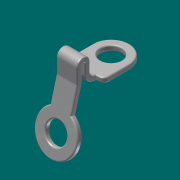
# Autodesk Inventor part: connector
Saved by Autodesk Inventor 2015 SP1 (Build 190203100, 203)
## iProperties
Created: 2015-06-26
Part Number: connector
Material: Generic
Document SubType Name: Modeling
Designer: Peter Mulkers
Density: 1 g/cm^3
Appearance: Steel
Author: Peter Mulkers
Autodesk Inventor part; units mm, degrees
ref_plane "YZ Plane" through (0, 0, 0) normal (1, 0, 0) x (0, 1, 0)
ref_plane "XZ Plane" through (0, 0, 0) normal (0, 1, 0) x (-1, 0, 0)
ref_plane "XY Plane" through (0, 0, 0) normal (0, 0, 1) x (1, 0, 0)
sketch "Sketch2" plane through (0, 0, 0) normal (0, 0, 1) x (1, 0, 0)
  circle A0 centre (0, -13) radius 1
  arc A1 (1.75, -13) -> (-1.75, -13) centre (0, -13) ccw
  line L0 (-1.75, -13) -> (-1.75, -15.4009)
  line L1 (1.75, -13) -> (1.75, -15.4009)
  line L2 (-1, -16) -> (1, -16)
  line L3 (-1, -16) -> (-1, -15.4677)
  line L4 (1, -16) -> (1, -15.4677)
  arc A2 (-1.75, -15.4009) -> (-1, -15.4677) centre (0, 0) ccw
  arc A3 (1, -15.4677) -> (1.75, -15.4009) centre (0, 0) ccw
  point P0 (0, -16)
  dimension "d22" = 2
  dimension "d23" = 13
  dimension "d24" = 3.5
  dimension "d26" = 2
  dimension "d27" = 3
  dimension "d28" = 15.5
  dimension "d29" = 15.5
  constraints: 10 end point, 6 point on circle, 4 centre point, 3 vertical, 2 coincident, 2 tangent, 2 vertical alignment, 1 horizontal, 1 midpoint, 1 parallel
  measures "d22" diameter of A0
  measures "d23" distance of A0.centre point (0, 0)
  measures "d24" diameter of A1
  measures "d26" distance of L2.start L2.end
  measures "d27" distance from line of A0.centre L2
  measures "d28" radius of A2
  measures "d29" radius of A3
extrude "Extrusion1" add sketch "Sketch2" along normal blind 0.5
fillet "Fillet1" radius 0.5 2 edges at (1.75, -15.4009, 0.25) (-1.75, -15.4009, 0.25)
sketch "Sketch3" plane through (-1, -16, 0.5) normal (0, -1, 0) x (1, 0, 0)
  line L0 (2, 0) -> (0, 0)
  line L1 (0, 0) -> (0, -2)
  line L2 (0, -2) -> (2, -2)
  line L3 (2, -2) -> (2, 0)
  constraints: 6 end point, 1 horizontal, 1 perpendicular, 1 vertical
edge flange "Flange1" height 2.5 angle 90 thickness 0.5 bend radius 0.5 thickness toward (0, -1, 0) relief straight relief width 0.5 relief depth 0.25 edges at (0, -16, 0) wall of the first edge with corners at (1, -16, 0.5) (-1, -16, 0.5) (-1, -16, 2.5) (1, -16, 2.5)
bend "Bend1"
corner "Corner1"
sketch "Sketch4" plane through (-1, -16, 1.875) normal (-1, 0, 0) x (0, -1, 0)
  line L0 (0, 0) -> (0.5, 0)
  arc A0 (0.75, 0) -> (0.5, 0) centre (0.625, 0) ccw
  line L1 (0.75, 0) -> (0.75, -1.375)
  line L2 (0.75, -1.375) -> (1.25, -1.375)
  line L3 (1.25, -1.375) -> (1.25, 0)
  arc A1 (1.25, 0) -> (0, 0) centre (0.625, 0) ccw
  point P0 (-0.125, 0)
  point P1 (-0.125, 0)
  constraints: 8 end point, 4 point on circle
hem "Hem1" sketch "Sketch4" thickness 0.5 along (1, 0, 0) edges at (0, -16, 2.5)
sketch "Sketch5" plane through (1, -17.25, 0.5) normal (0, 0.9659258, -0.258819) x (-1, 0, 0)
  line L0 (2, 0) -> (0, 0)
  line L1 (0, 0) -> (0, -1.9342)
  line L2 (0, -1.9342) -> (2, -1.9342)
  line L3 (2, -1.9342) -> (2, 0)
  constraints: 6 end point, 1 horizontal, 1 perpendicular, 1 vertical
edge flange "Flange2" height 2 angle 15 thickness 0.5 bend radius 0.5 thickness toward (0, 0.9659258, -0.258819) relief straight relief width 0.5 relief depth 0.25 edges at (0, -17.25, 0.5) wall of the first edge with corners at (-1, -17.25, 0.5) (1, -17.25, 0.5) (1, -17.7506, -1.3683) (-1, -17.7506, -1.3683)
bend "Bend2"
corner "Corner2"
sketch "Sketch6" plane through (-1, -17.7506, -1.3683) normal (0, -0.9659258, 0.258819) x (1, 0, 0)
  circle A0 centre (1, -2.1317) radius 1
  arc A1 (0, -0.3996) -> (2, -0.3996) centre (1, -2.1317) ccw
  line L0 (2, 1.8683) -> (0, 1.8683) projected
  line L1 (2, 1.8683) -> (2, -0.3996)
  line L2 (0, 1.8683) -> (0, -0.3996)
  line L3 (2, 1.8683) -> (0, 1.8683)
  point P0 (1, 5.9158)
  dimension "d60" = 2
  dimension "d61" = 4
  dimension "d62" = 4
  constraints: 6 end point, 2 centre point, 2 point on circle, 1 coincident, 1 parallel, 1 perpendicular, 1 tangent, 1 vertical
  measures "d60" diameter of A0
  measures "d61" diameter of A1
  measures "d62" distance from line of A0.centre L0
extrude "Extrusion2" add sketch "Sketch6" against normal blind 0.5
fillet "Fillet2" radius 0.125 48 edges at (1, -17.0776, -0.7883) (1, -16.7586, 0.4353) (1, -16.75, 1.2204) (1, -16.625, 2) (1, -16.5, 1.4375) (1, -16.2071, 0.2929) (1, -15.4839, 0) (1, -15.4839, 0.5) (1, -15.8536, 0.6464) (1, -16, 1.4375) (1, -16.625, 2.5) (1, -17.25, 1.2204) (1, -17.2543, 0.5006) (1, -17.5605, -0.6589) (0, -18.82, -5.3591) (-1, -17.5605, -0.6589) (-1, -18.3023, -3.4273) (0, -18.337, -5.4885) (-1, -17.0776, -0.7883) (-1, -17.8194, -3.5567) (-1, -17.2543, 0.5006) (-1, -17.25, 1.2204) (-1, -16.625, 2.5) (-1, -16, 1.4375) (-1, -15.8536, 0.6464) (-1, -15.4839, 0.5) (-1, -15.4839, 0) (-1, -16.2071, 0.2929) (-1, -16.5, 1.4375) (-1, -16.625, 2) (-1, -16.75, 1.2204) (-1, -16.7586, 0.4353) (-1.75, -13.9739, 0.5) (0, -11.25, 0.5) (1.75, -13.9739, 0.5) (1.618, -15.2863, 0.5) (1.1459, -15.4576, 0.5) (-1.1459, -15.4576, 0.5) (-1.618, -15.2863, 0.5) (-1, -13, 0.5) (1.1459, -15.4576, 0) (-1.75, -13.9739, 0) (0, -11.25, 0) (1.75, -13.9739, 0) (1.618, -15.2863, 0) (-1.1459, -15.4576, 0) (-1.618, -15.2863, 0) (-1, -13, 0)
equation "\"d43\" = BendReliefWidth"
equation "\"d44\" = BendReliefDepth"
equation "\"d45\" = MinimumRemnant"
equation "\"d46\" = BendRadius"
equation "\"d47\" = 4 * Thickness"
equation "\"d48\" = 0.5 * Thickness"
equation "\"d49\" = 0.5 * d48"
equation "\"d33\" = BendReliefWidth"
equation "\"d34\" = BendReliefDepth"
equation "\"d35\" = MinimumRemnant"
equation "\"d36\" = BendRadius"
equation "\"d39\" = BendRadius"
equation "\"d40\" = CornerReliefSize"
equation "\"d41\" = GapSize"
equation "\"d42\" = JacobiRadiusSize"
equation "\"d50\" = BendReliefWidth"
equation "\"d51\" = BendReliefDepth"
equation "\"d52\" = MinimumRemnant"
equation "\"d53\" = BendRadius"
equation "\"d56\" = BendRadius"
equation "\"d57\" = CornerReliefSize"
equation "\"d58\" = GapSize"
equation "\"d59\" = JacobiRadiusSize"
equation "\"BendRadius\" = Thickness"
equation "\"BendReliefWidth\" = Thickness"
equation "\"BendReliefDepth\" = 0.5 * Thickness"
equation "\"CornerReliefSize\" = 4 * Thickness"
equation "\"MinimumRemnant\" = 2 * Thickness"
equation "\"TransitionRadius\" = BendRadius"
equation "\"JacobiRadiusSize\" = BendRadius"
equation "\"GapSize\" = Thickness"
equation "\"Thickness\" = 0.5"
body "Solid1"
